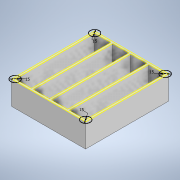
# Autodesk Inventor part: despartitor_jumate
Saved by Autodesk Inventor 2022.6 (Build 266554000, 554)
## iProperties
Created: 2026-01-12
Part Number: despartitor_jumate
Material: Generic
Document SubType Name: Modeling
Designer: Dragos Macovei
Density: 1 g/cm^3
Appearance: Default
Author: Dragos Macovei
Autodesk Inventor part; units mm, degrees
ref_plane "YZ Plane" through (0, 0, 0) normal (1, 0, 0) x (0, 1, 0)
ref_plane "XZ Plane" through (0, 0, 0) normal (0, 1, 0) x (-1, 0, 0)
ref_plane "XY Plane" through (0, 0, 0) normal (0, 0, 1) x (1, 0, 0)
sketch "Sketch1" plane through (0, 0, 0) normal (0, 1, 0) x (-1, 0, 0)
  line L0 (0, 0) -> (125, 0)
  line L1 (125, 0) -> (125, 140)
  line L2 (125, 140) -> (0, 140)
  line L3 (0, 140) -> (0, 0)
  line L4 (33.5, 3) -> (33.5, 137)
  line L5 (94.5, 3) -> (94.5, 137)
  line L6 (64, 3) -> (64, 137)
  line L7 (91.5, 3) -> (91.5, 137)
  line L8 (61, 3) -> (61, 137)
  line L9 (3, 3) -> (3, 137)
  line L10 (30.5, 3) -> (30.5, 137)
  line L11 (122, 3) -> (122, 137)
  line L12 (122, 137) -> (94.5, 137)
  line L13 (91.5, 137) -> (64, 137)
  line L14 (61, 137) -> (33.5, 137)
  line L15 (30.5, 137) -> (3, 137)
  line L16 (30.5, 3) -> (3, 3)
  line L17 (61, 3) -> (33.5, 3)
  line L18 (122, 3) -> (94.5, 3)
  line L19 (91.5, 3) -> (64, 3)
  point P0 (64, 70)
  point P1 (91.5, 70)
  dimension "d0" = 125
  dimension "d1" = 140
  dimension "d2" = 3
  dimension "d3" = 3
  dimension "d4" = 3
  dimension "d5" = 3
  dimension "d6" = 3
  dimension "d9" = 27.5
  dimension "d10" = 27.5
  dimension "d11" = 27.5
  constraints: 40 end point, 17 perpendicular, 2 midpoint, 2 parallel, 1 horizontal
  measures "d0" distance of L2.end L1.end
  measures "d1" distance of L1.end L0.end
  measures "d2" distance between parallel lines of L3 L9
  measures "d3" distance between parallel lines of L4 L10
  measures "d4" distance between parallel lines of L8 L6
  measures "d5" distance between parallel lines of L7 L5
  measures "d6" distance between parallel lines of L1 L11
  measures "d9" distance between parallel lines of L5 L11
  measures "d10" distance of point (64, 70) point (91.5, 70)
  measures "d11" distance between parallel lines of L4 L8
extrude "Extrusion1" add sketch "Sketch1" along normal blind 40
sketch "Sketch2" plane through (0, 40, 0) normal (0, 1, 0) x (1, 0, 0)
  line L0 (-30.5, -137) -> (-30.5, -3) projected
  line L1 (-125, 0) -> (-125, -140) projected
  line L2 (-125, -140) -> (0, -140) projected
  line L3 (0, -140) -> (0, 0) projected
  line L4 (0, 0) -> (-125, 0) projected
  line L5 (-30.5, -3) -> (-3, -3) projected
  line L6 (-3, -3) -> (-3, -137) projected
  line L7 (-3, -137) -> (-30.5, -137) projected
  line L8 (-30.5, -137) -> (-30.5, -3) projected
  line L9 (-91.5, -3) -> (-64, -3) projected
  line L10 (-64, -3) -> (-64, -137) projected
  line L11 (-64, -137) -> (-91.5, -137) projected
  line L12 (-91.5, -137) -> (-91.5, -3) projected
  line L13 (-122, -3) -> (-94.5, -3) projected
  line L14 (-94.5, -3) -> (-94.5, -137) projected
  line L15 (-94.5, -137) -> (-122, -137) projected
  line L16 (-122, -137) -> (-122, -3) projected
  line L17 (-61, -3) -> (-33.5, -3) projected
  line L18 (-33.5, -3) -> (-33.5, -137) projected
  line L19 (-33.5, -137) -> (-61, -137) projected
  line L20 (-61, -137) -> (-61, -3) projected
  line L21 (-30.5, -3) -> (-3, -3) projected
  circle A0 centre (-3, -3) radius 7.5
  circle A1 centre (-122, -3) radius 7.5
  line L22 (-122, -137) -> (-122, -3) projected
  circle A2 centre (-122, -137) radius 7.5
  line L23 (-3, -137) -> (-30.5, -137) projected
  circle A3 centre (-3, -137) radius 7.5
  dimension "d14" = 15
  dimension "d15" = 15
  dimension "d16" = 15
  dimension "d17" = 15
  constraints: 4 centre point, 4 coincident
  measures "d14" diameter of A0
  measures "d15" diameter of A1
  measures "d16" diameter of A2
  measures "d17" diameter of A3
equation "\"d3\" = d2"
equation "\"d4\" = d2"
equation "\"d5\" = d4"
equation "\"d6\" = d5"
equation "\"d10\" = d9"
equation "\"d11\" = d9"
equation "\"d7\" = d2"
body "Solid1"
